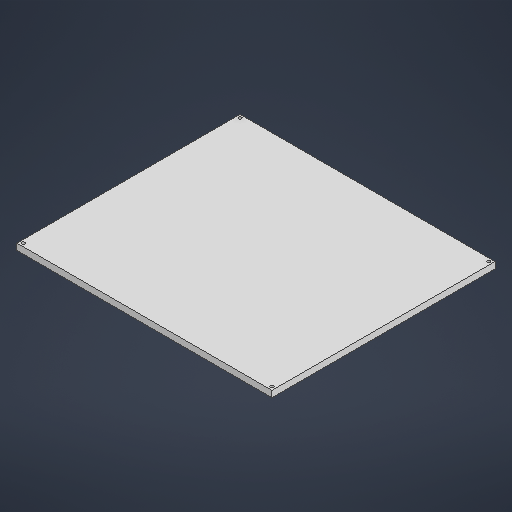
# Autodesk Inventor part: Enclosure Lid
Saved by Autodesk Inventor 2026.2 (Build 302298010, 298A)
## iProperties
Created: 2026-03-26
Part Number: Enclosure Lid
Material: Generic
Document SubType Name: Modeling
Designer: User
Density: 1 g/cm^3
Appearance: Default
Author: User
Autodesk Inventor part; units mm, degrees
ref_plane "YZ Plane" through (0, 0, 0) normal (1, 0, 0) x (0, 1, 0)
ref_plane "XZ Plane" through (0, 0, 0) normal (0, 1, 0) x (-1, 0, 0)
ref_plane "XY Plane" through (0, 0, 0) normal (0, 0, 1) x (1, 0, 0)
sketch "Sketch1" plane through (0, 0, 0) normal (0, 1, 0) x (-1, 0, 0)
  line L0 (200, 175) -> (-200, 175)
  line L1 (-200, 175) -> (-200, -175)
  line L2 (-200, -175) -> (200, -175)
  line L3 (200, -175) -> (200, 175)
  line L4 (200, 175) -> (-200, -175) construction
  line L5 (-200, 175) -> (200, -175) construction
  point P0 (0, 0)
  dimension "d0" = 400
  dimension "d1" = 350
  constraints: 12 end point, 2 midpoint, 2 parallel, 1 horizontal, 1 perpendicular
  measures "d0" distance of L2.end L1.end
  measures "d1" distance of L1.end L0.end
extrude "Extrusion1" add sketch "Sketch1" along normal blind 10
sketch "Sketch2" plane through (0, 10, 0) normal (0, 1, 0) x (1, 0, 0)
  line L0 (-200, -175) -> (200, -175) projected
  line L1 (-200, -175) -> (-190, -175)
  line L2 (-190, -175) -> (-190, -165)
  line L3 (-190, -165) -> (-200, -165)
  line L4 (-200, -165) -> (-200, -175)
  line L5 (200, 175) -> (-200, 175) projected
  line L6 (-200, 175) -> (-190, 175)
  line L7 (-190, 175) -> (-190, 165)
  line L8 (-190, 165) -> (-200, 165)
  line L9 (-200, 165) -> (-200, 175)
  line L10 (200, 175) -> (190, 175)
  line L11 (190, 175) -> (190, 165)
  line L12 (190, 165) -> (200, 165)
  line L13 (200, 165) -> (200, 175)
  line L14 (200, -175) -> (200, 175) projected
  line L15 (200, -175) -> (190, -175)
  line L16 (190, -175) -> (190, -165)
  line L17 (190, -165) -> (200, -165)
  line L18 (200, -165) -> (200, -175)
  point P0 (0, 0)
  point P1 (-195, -170)
  point P2 (-195, 170)
  point P3 (195, 170)
  point P4 (195, -170)
  dimension "d4" = 10
  dimension "d5" = 10
  dimension "d6" = 10
  dimension "d7" = 10
  dimension "d8" = 10
  dimension "d9" = 10
  dimension "d10" = 10
  dimension "d11" = 10
  constraints: 32 end point, 8 parallel, 4 horizontal, 4 perpendicular
  measures "d4" distance of L3.end L2.end
  measures "d5" distance of L2.end L1.end
  measures "d6" distance of L7.end L8.end
  measures "d7" distance of L6.end L7.end
  measures "d8" distance of L12.end L11.end
  measures "d9" distance of L11.end L10.end
  measures "d10" distance of L16.end L17.end
  measures "d11" distance of L15.end L16.end
hole "Hole1" at (-195, 10, -170) at (195, 10, -170) at (195, 10, 170) at (-195, 10, 170) direction (0, -1, 0) diameter 5 end through all
body "Solid1"
